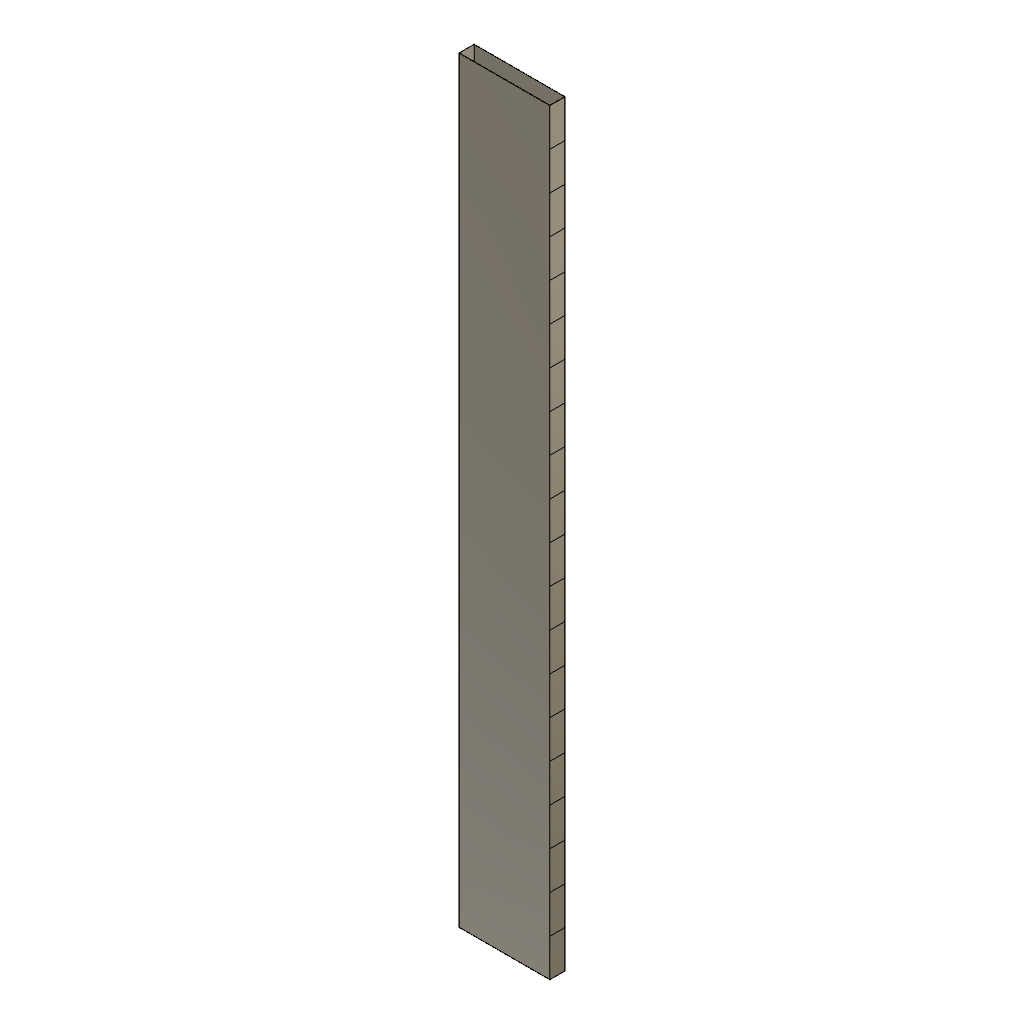
WB-01 Wing Box (Autodesk Fusion 360 design; units mm, degrees)
part number: 2026-10-18-11-50-24-168
description: ENG3081 wing box, thin-walled rectangular section, midline dimensions per the brief
part number: 2026-10-18-11-50-51-464
Autodesk Fusion 360 part; units mm, degrees
sketch "Box section" plane through (0, 0, 0) normal (0, 0, 1) x (1, 0, 0) in component "Wing Box"
  line L0 (198.1, -101.9) -> (1401.9, -101.9)
  line L1 (1401.9, -101.9) -> (1401.9, 101.9)
  line L2 (1401.9, 101.9) -> (198.1, 101.9)
  line L3 (198.1, 101.9) -> (198.1, -101.9)
  line L4 (201.9, -98.1) -> (1398.1, -98.1)
  line L5 (1398.1, -98.1) -> (1398.1, 98.1)
  line L6 (1398.1, 98.1) -> (201.9, 98.1)
  line L7 (201.9, 98.1) -> (201.9, -98.1)
  line L8 (0, 0) -> (2000, 0) construction
  point P0 (400, 0)
  dimension "d9" = 1203.8
  dimension "d10" = 203.8
  dimension "d11" = 1196.2
  dimension "d12" = 196.2
  dimension "d13" = 198.1
  dimension "d14" = 101.9
  dimension "d15" = 201.9
  dimension "d16" = 98.1
  dimension "d17" = 2000
  dimension "d18" = 400
  constraint horizontal L0
  constraint horizontal L2
  constraint vertical L1
  constraint vertical L3
  constraint horizontal L4
  constraint horizontal L6
  constraint vertical L5
  constraint vertical L7
  constraint horizontal L8
  constraint coincident L8 P0
  measures "d9" horizontal distance of L0.start L0.end
  measures "d10" vertical distance of L0.end L1.end
  measures "d11" horizontal distance of L4.start L4.end
  measures "d12" vertical distance of L4.end L5.end
  measures "d13" horizontal distance of L8.start L0.start
  measures "d14" vertical distance of L8.start L0.start
  measures "d15" horizontal distance of L8.start L4.start
  measures "d16" vertical distance of L8.start L4.start
  measures "d17" horizontal distance of L8.start L8.end
  measures "d18" horizontal distance of L8.start P0
extrude "Wing box" add sketch "Box section" along normal blind 10000 in component "Wing Box"
ref_plane "WorkPlane1" through (0, 0, 500) normal (0, 0, 1) x (1, 0, 0) in component "Wing Box"
ref_plane "WorkPlane2" through (0, 0, 1000) normal (0, 0, 1) x (1, 0, 0) in component "Wing Box"
ref_plane "WorkPlane3" through (0, 0, 1500) normal (0, 0, 1) x (1, 0, 0) in component "Wing Box"
ref_plane "WorkPlane4" through (0, 0, 2000) normal (0, 0, 1) x (1, 0, 0) in component "Wing Box"
ref_plane "WorkPlane5" through (0, 0, 2500) normal (0, 0, 1) x (1, 0, 0) in component "Wing Box"
ref_plane "WorkPlane6" through (0, 0, 3000) normal (0, 0, 1) x (1, 0, 0) in component "Wing Box"
ref_plane "WorkPlane7" through (0, 0, 3500) normal (0, 0, 1) x (1, 0, 0) in component "Wing Box"
ref_plane "WorkPlane8" through (0, 0, 4000) normal (0, 0, 1) x (1, 0, 0) in component "Wing Box"
ref_plane "WorkPlane9" through (0, 0, 4500) normal (0, 0, 1) x (1, 0, 0) in component "Wing Box"
ref_plane "WorkPlane10" through (0, 0, 5000) normal (0, 0, 1) x (1, 0, 0) in component "Wing Box"
ref_plane "WorkPlane11" through (0, 0, 5500) normal (0, 0, 1) x (1, 0, 0) in component "Wing Box"
ref_plane "WorkPlane12" through (0, 0, 6000) normal (0, 0, 1) x (1, 0, 0) in component "Wing Box"
ref_plane "WorkPlane13" through (0, 0, 6500) normal (0, 0, 1) x (1, 0, 0) in component "Wing Box"
ref_plane "WorkPlane14" through (0, 0, 7000) normal (0, 0, 1) x (1, 0, 0) in component "Wing Box"
ref_plane "WorkPlane15" through (0, 0, 7500) normal (0, 0, 1) x (1, 0, 0) in component "Wing Box"
ref_plane "WorkPlane16" through (0, 0, 8000) normal (0, 0, 1) x (1, 0, 0) in component "Wing Box"
ref_plane "WorkPlane17" through (0, 0, 8500) normal (0, 0, 1) x (1, 0, 0) in component "Wing Box"
ref_plane "WorkPlane18" through (0, 0, 9000) normal (0, 0, 1) x (1, 0, 0) in component "Wing Box"
ref_plane "WorkPlane19" through (0, 0, 9500) normal (0, 0, 1) x (1, 0, 0) in component "Wing Box"
split_face "Load strips" 2 faces at (1401.9, -33.9667, 3333.3333) (198.1, 33.9667, 3333.3333) by plane through (0, 0, 500) normal (0, 0, 1) in component "Wing Box"
component "Wing Box" placed x (1, 0, 0) y (0, 1, 0) z (0, 0, 1) at (0, 0, 0)
equation "SemiSpan = 10 m" comment "Root to tip, ENG3081 brief"
equation "ChordLength = 2 m" comment "Wing chord, constant"
equation "BoxWidth = 1.2 m" comment "Front web to rear web, midline"
equation "BoxDepth = 0.2 m" comment "Lower to upper cover, midline"
equation "BoxLE = 0.2 m" comment "Front web midline from the leading edge"
equation "WallThickness = 3.8 mm" comment "All walls; design variable"
equation "CentreOfPressure = 0.4 m" comment "20 % chord, constant along the span"
equation "LoadStripCount = 20" comment "Spanwise strips on the outer web faces used to apply the elliptical lift"
equation "d9 = BoxWidth + WallThickness"
equation "d10 = BoxDepth + WallThickness"
equation "d11 = BoxWidth - WallThickness"
equation "d12 = BoxDepth - WallThickness"
equation "d13 = BoxLE - WallThickness / 2"
equation "d14 = ( BoxDepth + WallThickness ) / 2"
equation "d15 = BoxLE + WallThickness / 2"
equation "d16 = ( BoxDepth - WallThickness ) / 2"
equation "d17 = ChordLength"
equation "d18 = CentreOfPressure"
equation "d19 = SemiSpan"
equation "d21 = SemiSpan * 1 / LoadStripCount"
equation "d23 = SemiSpan * 2 / LoadStripCount"
equation "d25 = SemiSpan * 3 / LoadStripCount"
equation "d27 = SemiSpan * 4 / LoadStripCount"
equation "d29 = SemiSpan * 5 / LoadStripCount"
equation "d31 = SemiSpan * 6 / LoadStripCount"
equation "d33 = SemiSpan * 7 / LoadStripCount"
equation "d35 = SemiSpan * 8 / LoadStripCount"
equation "d37 = SemiSpan * 9 / LoadStripCount"
equation "d39 = SemiSpan * 10 / LoadStripCount"
equation "d41 = SemiSpan * 11 / LoadStripCount"
equation "d43 = SemiSpan * 12 / LoadStripCount"
equation "d45 = SemiSpan * 13 / LoadStripCount"
equation "d47 = SemiSpan * 14 / LoadStripCount"
equation "d49 = SemiSpan * 15 / LoadStripCount"
equation "d51 = SemiSpan * 16 / LoadStripCount"
equation "d53 = SemiSpan * 17 / LoadStripCount"
equation "d55 = SemiSpan * 18 / LoadStripCount"
equation "d57 = SemiSpan * 19 / LoadStripCount"
named bodies: "Wing Box"
